Autodesk Fusion 360 part; units mm, degrees
(part 7 of 7)
component "rear left public turning fork" placed x (1, 0, 0) y (0, 1, 0) z (0, 0, 1) at (0, 0, 0)
component "rear left public wheel axle" placed x (1, 0, 0) y (0, 1, 0) z (0, 0, 1) at (0, 0, 0)
component "rear right public turning fork" placed x (1, 0, 0) y (0, 1, 0) z (0, 0, 1) at (0, 0, 0)
component "rear right public wheel axle" placed x (1, 0, 0) y (0, 1, 0) z (0, 0, 1) at (0, 0, 0)
component "right blue side bumper" placed x (1, 0, 0) y (0, 1, 0) z (0, 0, 1) at (0, -378, 48) in component "rail synchronizing tie"
component "front right module tab spacer 1" placed x (1, 0, 0) y (0, 1, 0) z (0, 0, 1) at (303.05, -198, 78.32) in component "rear right tab 1-1 socket screw"
equation "d1905 = -( 4.50 mm )"
equation "d1909 = -( 4.50 mm )"
equation "d1913 = -( 4.50 mm )"
equation "d1917 = -( 4.50 mm )"
equation "d1949 = -( 4.50 mm )"
equation "d1953 = -( 4.50 mm )"
equation "d1957 = -( 4.50 mm )"
equation "d1961 = -( 4.50 mm )"
equation "d1977 = -( 44.00 mm )"
equation "d1981 = -( 44.00 mm )"
named bodies: "left blue side bumper", "left blue front bumper", "right blue side bumper", "right blue front bumper", "rear blue bumper", "left electronics deck", "right electronics deck", "fore electronics deck bridge", "aft electronics deck bridge", "battery cradle floor", "battery cradle wall -44", "battery cradle wall 43", "battery secured envelope", "distribution enclosure reserve", "robot controller reserve", "field radio reserve", "drive controller reserve 1", "drive controller reserve 2", "drive controller reserve 3", "drive controller reserve 4", "drive controller reserve 5", "drive controller reserve 6", "drive controller reserve 7", "drive controller reserve 8", "hopper back panel", "right hopper wall", "right hopper front wing", "right cross feed deck", "right front elevator upright", "right rear elevator upright", "right elevator upper tie", "right inside lift belt", "right outside lift belt", "right lift shelf 1", "right lift shelf 2", "right lift shelf 3", "right lift shelf 4", "right intake ramp", "left hopper wall", "left hopper front wing", "left cross feed deck", "left front elevator upright", "left rear elevator upright", "left elevator upper tie", "left inside lift belt", "left outside lift belt", "left lift shelf 1", "left lift shelf 2", "left lift shelf 3", "left lift shelf 4", "left intake ramp", "central fore-aft feed deck", "left lower lift stub shaft", "right lower lift stub shaft", "left upper lift stub shaft", "right upper lift stub shaft", "ground intake roller", "right intake bearing arm", "right intake pivot plate", "right intake pivot axle", "right intake journal", "right upper head cheek", "left intake bearing arm", "left intake pivot plate", "left intake pivot axle", "left intake journal", "left upper head cheek", "right scoring wheel", "right scoring spindle", "right upper guide", "right scoring bearing bridge -33", "right scoring bearing bridge 33", "left scoring wheel", "left scoring spindle", "left upper guide", "left scoring bearing bridge -33", "left scoring bearing bridge 33", "left feed diverter pivot", "right feed diverter pivot", "feed diverter vane", "right public scoring motor envelope", "left public scoring motor envelope", "rear lift custody gate", "front lift custody guide", "left mast", "left aft mast", "left upper bearing plate", "left lower bearing plate", "left lead screw envelope", "left lift motor envelope", "left reduction envelope", "left driven nut", "left nut link", "left crosshead cheek", "left forward carriage sleeve", "left aft carriage sleeve", "left extension sleeve", "left sleeve pedestal", "left extending rail", "left crown hook", "right mast", "right aft mast", "right upper bearing plate", "right lower bearing plate", "right lead screw envelope", "right lift motor envelope", "right reduction envelope", "right driven nut", "right nut link", "right crosshead cheek", "right forward carriage sleeve", "right aft carriage sleeve", "right extension sleeve", "right sleeve pedestal", "right extending rail", "right crown hook", "crosshead lift bridge", "rail synchronizing tie", "extension bearing beam", "extension rear bearing and stop", "extension forward bearing", "extension screw envelope", "extension deployment nut", "extension nut hanger", "extension motor envelope", "extension motor foot", "rear perimeter tube", "right perimeter tube", "right front return", "right floor sill", "rear right hopper post", "front right hopper post", "left perimeter tube", "left front return", "left floor sill", "rear left hopper post", "front left hopper post", "rear deck crossmember", "rear right crossmember backing plate", "rear left crossmember backing plate", "front deck crossmember", "front right crossmember backing plate", "front left crossmember backing plate", "front left module tab spacer 1", "front left module tab spacer 2", "front right module tab spacer 1", "front right module tab spacer 2", "rear left module tab spacer 1", "rear left module tab spacer 2", "rear right module tab spacer 1", "rear right module tab spacer 2", "front left rail mount 1-1 weld boss", "front left rail mount 1-1 M6 cap screw", "front left rail mount 1-2 weld boss", "front left rail mount 1-2 M6 cap screw", "front left tab 1-1 socket screw", "front left tab 1-1 locknut", "front left tab 1-2 socket screw", "front left tab 1-2 locknut", "front left rail mount 2-1 weld boss", "front left rail mount 2-1 M6 cap screw", "front left rail mount 2-2 weld boss", "front left rail mount 2-2 M6 cap screw", "front left tab 2-1 socket screw", "front left tab 2-1 locknut", "front left tab 2-2 socket screw", "front left tab 2-2 locknut", "front right rail mount 1-1 weld boss", "front right rail mount 1-1 M6 cap screw", "front right rail mount 1-2 weld boss", "front right rail mount 1-2 M6 cap screw", "front right tab 1-1 socket screw", "front right tab 1-1 locknut", "front right tab 1-2 socket screw", "front right tab 1-2 locknut", "front right rail mount 2-1 weld boss", "front right rail mount 2-1 M6 cap screw", "front right rail mount 2-2 weld boss", "front right rail mount 2-2 M6 cap screw", "front right tab 2-1 socket screw", "front right tab 2-1 locknut", "front right tab 2-2 socket screw", "front right tab 2-2 locknut", "rear left rail mount 1-1 weld boss", "rear left rail mount 1-1 M6 cap screw", "rear left rail mount 1-2 weld boss", "rear left rail mount 1-2 M6 cap screw", "rear left tab 1-1 socket screw", "rear left tab 1-1 locknut", "rear left tab 1-2 socket screw", "rear left tab 1-2 locknut", "rear left rail mount 2-1 weld boss", "rear left rail mount 2-1 M6 cap screw", "rear left rail mount 2-2 weld boss", "rear left rail mount 2-2 M6 cap screw", "rear left tab 2-1 socket screw", "rear left tab 2-1 locknut", "rear left tab 2-2 socket screw", "rear left tab 2-2 locknut", "rear right rail mount 1-1 weld boss", "rear right rail mount 1-1 M6 cap screw", "rear right rail mount 1-2 weld boss", "rear right rail mount 1-2 M6 cap screw", "rear right tab 1-1 socket screw", "rear right tab 1-1 locknut", "rear right tab 1-2 socket screw", "rear right tab 1-2 locknut", "rear right rail mount 2-1 weld boss", "rear right rail mount 2-1 M6 cap screw", "rear right rail mount 2-2 weld boss", "rear right rail mount 2-2 M6 cap screw", "rear right tab 2-1 socket screw", "rear right tab 2-1 locknut", "rear right tab 2-2 socket screw", "rear right tab 2-2 locknut", "front left public drive housing", "front left public motor reserve", "front left public turning fork", "front left public wheel axle", "front left public wheel", "front right public drive housing", "front right public motor reserve", "front right public turning fork", "front right public wheel axle", "front right public wheel", "rear left public drive housing", "rear left public motor reserve", "rear left public turning fork", "rear left public wheel axle", "rear left public wheel", "rear right public drive housing", "rear right public motor reserve", "rear right public turning fork", "rear right public wheel axle", "rear right public wheel"
